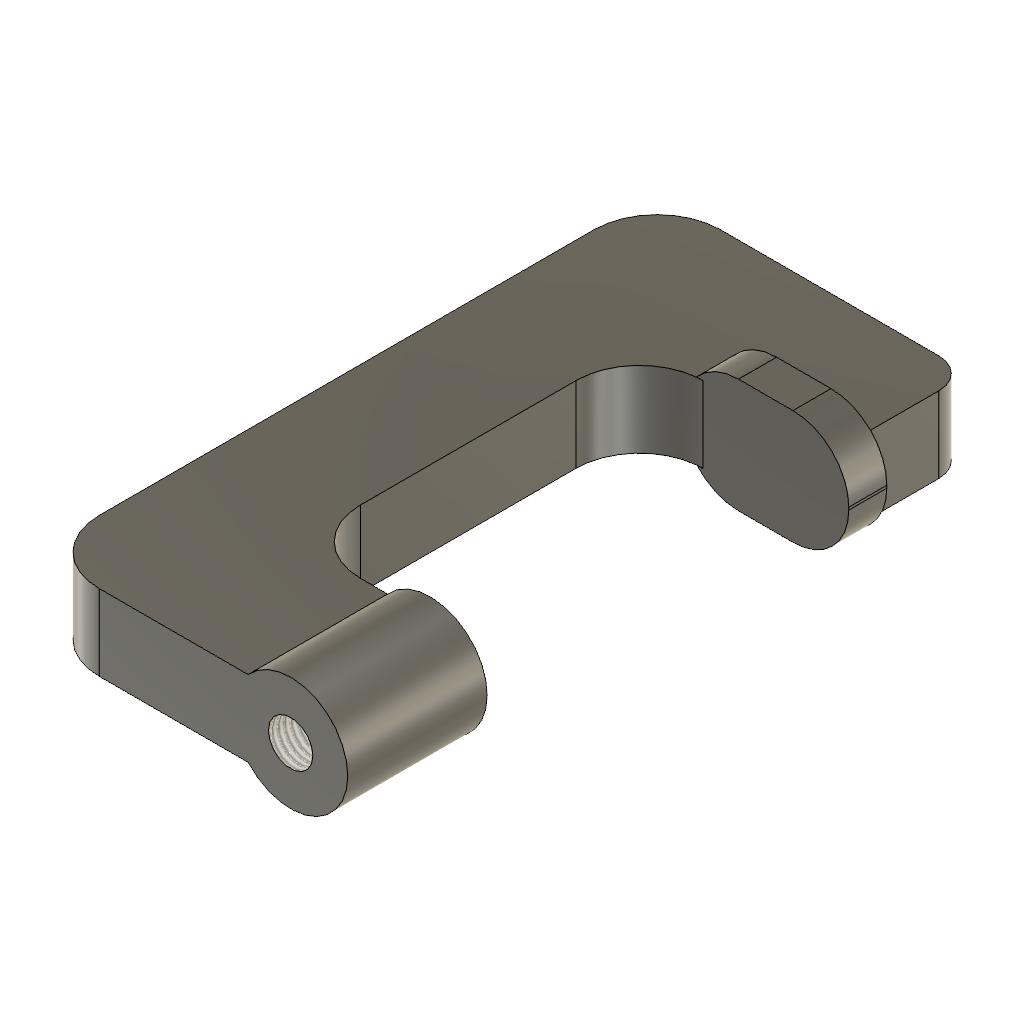
Untitled (Autodesk Fusion 360 design; units mm, degrees)
part number: 2026-10-15-13-43-15-240
Autodesk Fusion 360 part; units mm, degrees
sketch "Sketch1" plane through (0, 0, 0) normal (0, 0, 1) x (1, 0, 0)
  line L0 (0, 73.6549) -> (0, -171.3451)
  line L1 (0, -171.3451) -> (123, -171.3451)
  line L2 (123, -171.3451) -> (123, -151.3451)
  line L3 (0, -171.3451) -> (123, -151.3451)
  line L4 (123, -151.3451) -> (123, -116.3451)
  line L5 (0, 73.6549) -> (123, 73.6549)
  line L6 (123, 73.6549) -> (123, 53.6549)
  line L7 (123, 53.6549) -> (123, 18.6549)
  line L8 (0, 73.6549) -> (123, 53.6549)
  line L9 (123, -116.3451) -> (48, -116.3451)
  line L10 (123, 18.6549) -> (48, 18.6549)
  line L11 (48, -116.3451) -> (48, 18.6549)
  dimension "d1" = 245
  dimension "d2" = 123
  dimension "d3" = 20
  dimension "d4" = 35
  dimension "d5" = 123
  dimension "d6" = 20
  dimension "d7" = 35
  dimension "d8" = 75
  dimension "d9" = 75
  constraint vertical L0
  constraint perpendicular L0 L1
  constraint perpendicular L1 L2
  constraint parallel L2 L4
  constraint perpendicular L0 L5
  constraint perpendicular L5 L6
  constraint perpendicular L5 L7
  constraint perpendicular L4 L9
  constraint perpendicular L7 L10
  measures "d1" distance of L0.start L0.end
  measures "d2" distance of L0.end L1.end
  measures "d3" distance of L1.end L2.end
  measures "d4" distance of L2.end L4.end
  measures "d5" distance of L0.start L5.end
  measures "d6" distance of L5.end L6.end
  measures "d7" distance of L6.end L7.end
  measures "d8" distance of L4.end L9.end
  measures "d9" distance of L7.end L10.end
extrude "Extrude1" add sketch "Sketch1" along normal blind 30
sketch "Sketch2" plane through (0, -171.3451, 0) normal (0, -1, 0) x (1, 0, 0)
  line L0 (0, 0) -> (123, 0)
  line L1 (123, 0) -> (123, 30)
  line L2 (123, 30) -> (0, 30)
  line L3 (0, 30) -> (0, 0)
  line L4 (123, 30) -> (100.5, 30)
  line L5 (100.5, 30) -> (100.5, 15)
  circle A0 centre (100.5, 15) radius 22.5
  dimension "d12" = 22.5
  dimension "d13" = 15
  dimension "d14" = 45
  constraint coincident L1.end L2.start
  constraint perpendicular L1 L4
  constraint perpendicular L0 L5
  constraint coincident L5.end A0.centre
  measures "d12" distance of L1.end L4.end
  measures "d13" distance of L4.end L5.end
  measures "d14" diameter of A0
extrude "Extrude2" add sketch "Sketch2" against normal blind 55 contours L0 A0 | L2 L4 A0
sketch "Sketch3" plane through (0, -171.3451, 0) normal (0, -1, 0) x (1, 0, 0)
  line L0 (0, 0) -> (83.7295, 0)
  arc A0 (83.7295, 0) -> (117.2705, 0) centre (100.5, 15) ccw
  line L1 (117.2705, 0) -> (123, 0)
  line L2 (123, 0) -> (123, 30)
  line L3 (123, 30) -> (117.2705, 30)
  arc A1 (117.2705, 30) -> (83.7295, 30) centre (100.5, 15) ccw
  line L4 (83.7295, 30) -> (0, 30)
  line L5 (0, 30) -> (0, 0)
  line L6 (123, 30) -> (100.5, 30)
  line L7 (100.5, 30) -> (100.5, 15)
  line L8 (100.5, 15) -> (123, 15)
  line L9 (123, 15) -> (123, 30)
  circle A2 centre (100.5, 15) radius 22.5
  circle A3 centre (100.5, 15) radius 10
  dimension "d17" = 22.5
  dimension "d18" = 15
  dimension "d19" = 20
  constraint horizontal L6
  constraint vertical L7
  constraint horizontal L8
  constraint vertical L9
  constraint coincident L2.end L3.start
  constraint concentric A0 A2
  constraint concentric A2 A3
  measures "d17" distance of L2.end L6.end
  measures "d18" distance of L2.end L8.end
  measures "d19" diameter of A3
extrude "Extrude3" cut sketch "Sketch3" against normal blind 90 contours L1 L2 A2 | L2 L3 L6 L9 A2 | L7 L8 A3 | L7 L8 A3
fillet "Fillet1" radius 25 4 edges at (48, 18.6549, 15) (48, -116.3451, 15) (0, -171.3451, 15) (0, 73.6549, 15)
sketch "Sketch4" plane through (0, 18.6549, 0) normal (0, -1, 0) x (1, 0, 0)
  line L0 (73, 30) -> (73, 0)
  line L1 (73, 0) -> (123, 0)
  line L2 (123, 0) -> (123, 30)
  line L3 (123, 30) -> (73, 30)
  line L4 (123, 30) -> (117.2705, 30)
  line L5 (123, 15) -> (123, 30)
  circle A0 centre (100.5, 15) radius 22.5
  line L6 (130.5, -7.5) -> (70.5, -7.5)
  line L7 (70.5, -7.5) -> (70.5, 37.5)
  line L8 (70.5, 37.5) -> (130.5, 37.5)
  line L9 (130.5, 37.5) -> (130.5, -7.5)
  line L10 (130.5, -7.5) -> (70.5, 37.5) construction
  line L11 (70.5, -7.5) -> (130.5, 37.5) construction
  point P0 (100.5, 15)
  dimension "d25" = 15
  dimension "d26" = 45
  dimension "d27" = 60
  dimension "d28" = 45
  constraint horizontal L4
  constraint vertical L5
  constraint coincident L2.end L3.start
  constraint horizontal L6
  constraint perpendicular L6 L7
  constraint parallel L6 L8
  constraint parallel L7 L9
  constraint coincident L10 P0
  constraint coincident L11 P0
  constraint coincident A0 L4.end
  measures "d25" distance of L2.end L5.start
  measures "d26" diameter of A0
  measures "d27" distance of L7.end L8.end
  measures "d28" distance of L6.end L7.end
extrude "Extrude4" add sketch "Sketch4" against normal blind 15 contours L0 L1 L3 A0 L6 L7 L8 | L3 A0 | L1 A0 | L1 L2 L3 L4 L5 A0 L6 L8 L9
fillet "Fillet2" radius 22 4 edges at (70.5, 26.1549, 37.5) (130.5, 26.1549, 37.5) (130.5, 26.1549, -7.5) (70.5, 26.1549, -7.5)
fillet "Fillet3" radius 12 1 edges at (123, 73.6549, 15)
thread "Thread1" "ISO Metric profile 20.0 M20x2.5 M20x2.5 6H" major diameter 20.2925 minor diameter 17.519 pitch 2.5 angle 60 resizes the face on face at (110.4503, -134.6784, 14.0043)
